Metcal 910-WW kolb 10cc (Autodesk Fusion 360 design; units mm, degrees)
Autodesk Fusion 360 part; units mm, degrees
sketch "Sketch1" plane through (0, 0, 0) normal (0, 1, 0) x (1, 0, 0)
sketch "Sketch2" plane through (0, 0, 0) normal (1, 0, 0) x (0, 0, -1)
  line L0 (7.215, 3.7) -> (7.215, 4.05)
  line L1 (7.215, 3.7) -> (0, 0)
  line L2 (7.88, 4.05) -> (7.88, 6.8727)
  line L3 (7.88, 4.05) -> (7.215, 4.05)
  line L4 (7.88, 11.52) -> (7.88, 10.32)
  line L5 (7.35, 8.8942) -> (7.35, 7.9742)
  arc A0 (7.88, 10.32) -> (7.88, 4.05) centre (16.8869, 7.185) ccw
  line L6 (7.18, 11.52) -> (7.18, 10.4362)
  arc A1 (7.18, 10.4362) -> (6.9438, 4.75) centre (16.8869, 7.185) ccw
  line L7 (6.9438, 4.75) -> (6.515, 4.75)
  line L8 (6.515, 4.1277) -> (6.515, 4.75)
  line L9 (6.515, 4.1277) -> (-0.3194, 0.6229)
  line L10 (2, 1.0256) -> (2, 3.5)
  line L11 (2, 3.5) -> (0, 3.5)
  line L12 (0, 3.5) -> (0, 0)
  line L13 (7.18, 11.52) -> (7.88, 11.52)
  dimension "d1" = 7.215
  dimension "d2" = 0.35
  dimension "d3" = 3.7
  dimension "d4" = 7.88
  dimension "d5" = 7.88
  dimension "d6" = 6.27
  dimension "d7" = 7.35
  dimension "d9" = 1.2
  dimension "d10" = 0.7
  dimension "d11" = 2
  dimension "d12" = 3.5
  constraint vertical L0
  constraint coincident L1.end L12.end
  constraint vertical L2
  constraint perpendicular L2 L3
  constraint vertical L4
  constraint vertical L5
  constraint tangent L5 A0
  constraint coincident L1 L10.start
  constraint vertical L10
  constraint perpendicular L10 L11
  constraint perpendicular L11 L12
  constraint perpendicular L4 L13
  measures "d1" horizontal distance of L0.start L1.end
  measures "d2" distance of L0.start L0.end
  measures "d3" vertical distance of L1.end L0.start
  measures "d4" distance of L1.end L2
  measures "d5" horizontal distance of L1.end L4.start
  measures "d6" distance of L2.start L4.end
  measures "d7" distance of L1.end L5
  measures "d9" distance of L4.start L4.end
  measures "d11" distance of L1.end L10
  measures "d12" vertical distance of L1.end L10.end
revolve "Revolve1" add sketch "Sketch2" angle 360 about axis through (0, 3.5, 0) along (0, -1, 0)
equation "d1 = ( 14.43 / 2 ) * 1 mm"
equation "d4 = ( 15.76 / 2 ) * 1 mm"
equation "d5 = d4"
equation "d6 = 7.47 mm - 1.2 mm"
equation "d7 = ( 14.7 / 2 ) * 1 mm"
